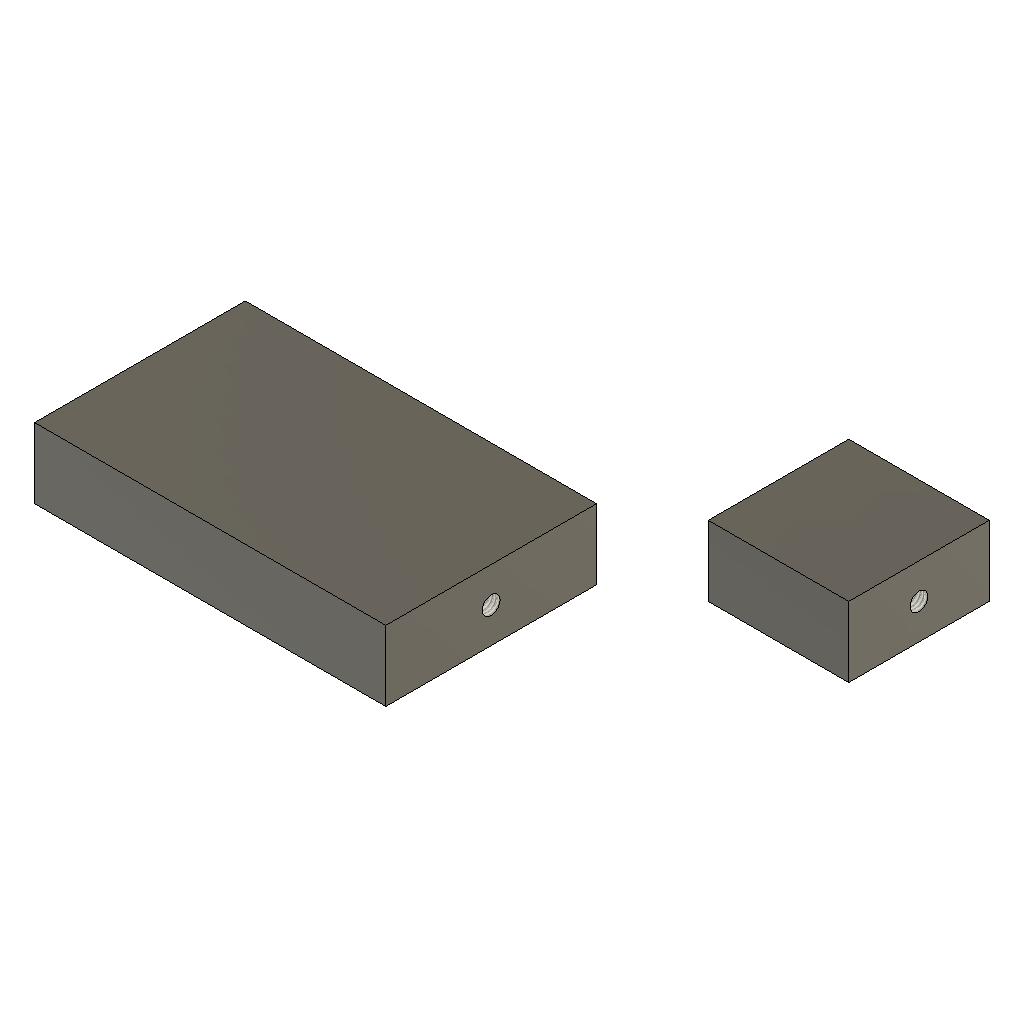
steel_test_articles (Autodesk Fusion 360 design; units mm, degrees)
part number: 2026-09-14-07-09-12-489
Autodesk Fusion 360 part; units mm, degrees
sketch "Sketch1" plane through (0, 0, 0) normal (0, 0, 1) x (1, 0, 0)
  line L0 (-25, -20.9039) -> (25, -20.9039)
  line L1 (25, -20.9039) -> (25, -50.9039)
  line L2 (25, -50.9039) -> (-25, -50.9039)
  line L3 (-25, -50.9039) -> (-25, -20.9039)
  line L4 (35, 5) -> (55, 5)
  line L5 (55, 5) -> (55, -15)
  line L6 (55, -15) -> (35, -15)
  line L7 (35, -15) -> (35, 5)
  dimension "d1" = 50
  dimension "d2" = 30
  constraint horizontal L0
  constraint vertical L1
  constraint horizontal L2
  constraint vertical L3
  constraint horizontal L4
  constraint vertical L5
  constraint horizontal L6
  constraint vertical L7
  measures "d1" distance of L0.start L0.end
  measures "d2" distance of L0.start L2.end
extrude "Extrude1" add sketch "Sketch1" along normal blind 10 makes body 1 at (-8.3333, -30.9039, 0) makes body 2 at (41.6667, -1.6667, 0)
hole "Hole1" at (55, -5, 5) direction (-1, 0, 0) diameter 2.529 depth 7 tip angle 118 bodies 2
thread "Thread1" "ISO Metric profile 3.0 M3x0.5 M3x0.5 6H" major diameter 3.086 minor diameter 2.529 pitch 0.5 angle 60 resizes the face on face at (52.6667, -4.937, 3.7371) on bodies 2
hole "Hole2" at (25, -35.9039, 5) direction (-1, 0, 0) diameter 2.529 depth 8 tip angle 118 bodies 1
thread "Thread2" "ISO Metric profile 3.0 M3x0.5 M3x0.5 6H" thread offset 0 thread depth 7.4
